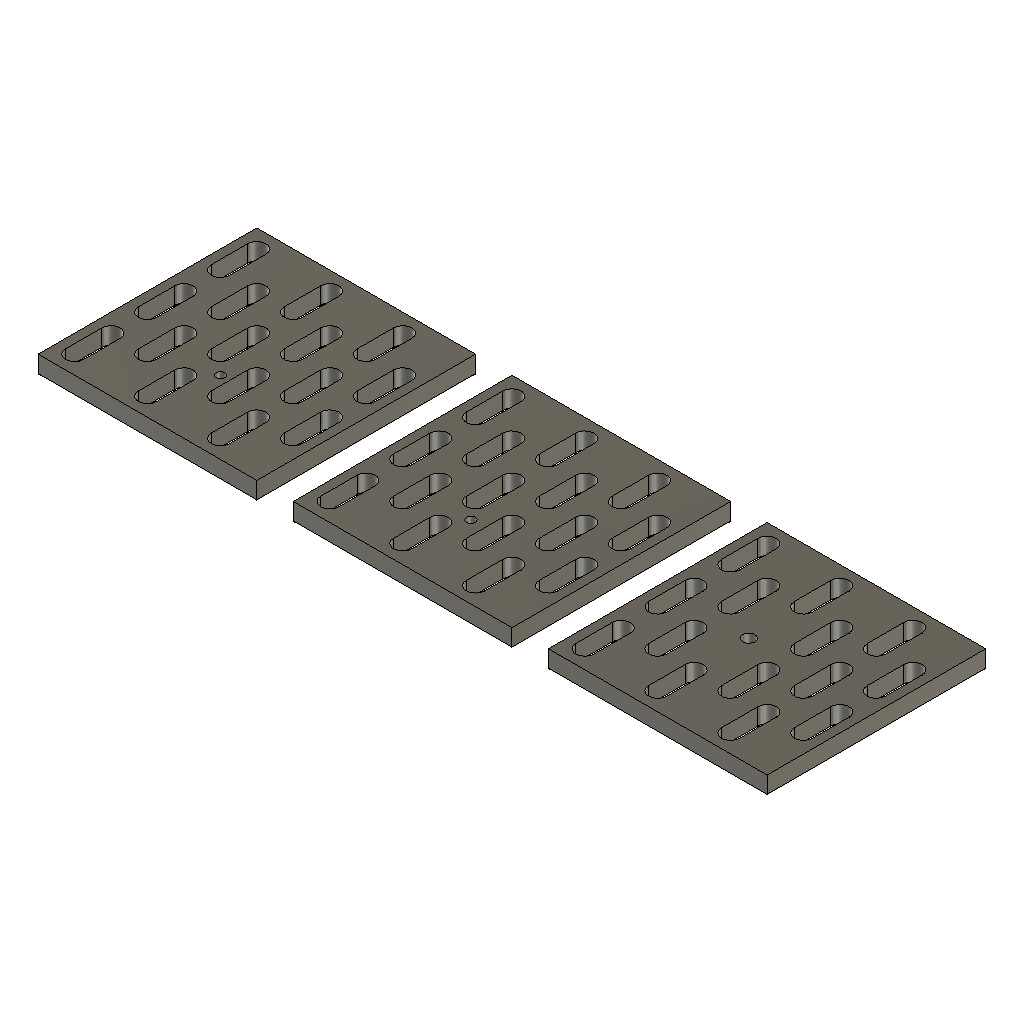
mounting-comparison (Autodesk Fusion 360 design; units mm, degrees)
part number: 2026-10-31-19-28-55-188
part number: 2026-10-31-19-28-55-479
part number: 2026-10-31-19-28-58-749
part number: 2026-10-31-19-29-04-549
Autodesk Fusion 360 part; units mm, degrees
(part 1 of 2)
sketch "Coupon blank sketch" plane through (0, 0, 0) normal (0, 0, 1) x (1, 0, 0) in component "Original M2"
  line L0 (0, 0) -> (60, 0)
  line L1 (60, 0) -> (60, 60)
  line L2 (60, 60) -> (0, 60)
  line L3 (0, 60) -> (0, 0)
  dimension "d68" = 60
  dimension "d69" = 60
  constraint horizontal L0
  constraint vertical L1
  constraint horizontal L2
  constraint vertical L3
  constraint vertical L0.start L3.end
  constraint horizontal L0.start L3.end
  measures "d68" horizontal distance of L0.start L0.end
  measures "d69" vertical distance of L0.end L1.end
extrude "Coupon blank" add sketch "Coupon blank sketch" along normal blind 5 makes body 1 in component "Original M2"
sketch "Slot 0 10 constrained seed" plane through (0, 0, 0) normal (0, 0, 1) x (1, 0, 0) in component "Original M2"
  line L0 (7.5, 5) -> (7.5, 15)
  arc A0 (7.5, 15) -> (2.5, 15) centre (5, 15) ccw
  line L1 (2.5, 15) -> (2.5, 5)
  arc A1 (2.5, 5) -> (7.5, 5) centre (5, 5) ccw
  line L2 (5, 5) -> (5, 15) construction
  line L3 (5, 5) -> (15, 5) construction
  dimension "d72" = 5
  dimension "d73" = 10
  dimension "d74" = 90
  dimension "d75" = 10
  dimension "d76" = 5
  dimension "d77" = 5
  constraint tangent L0 A0
  constraint tangent A0 L1
  constraint tangent L1 A1
  constraint tangent L0 A1
  constraint parallel L0 L1
  constraint horizontal L3
  measures "d72" diameter of A0
  measures "d73" distance of A1.centre A0.centre
  measures "d74" angle of L2 L3
  measures "d75" horizontal distance of A1.centre L3.end
  measures "d76" horizontal distance of origin A1.centre
  measures "d77" vertical distance of origin A1.centre
extrude "Slot 0 10 through cut" cut sketch "Slot 0 10 constrained seed" along normal blind 5 bodies 1 in component "Original M2"
pattern_linear "Slot 0 10 lattice" count 1 spacing 20 along (1, 0, 0) of "Slot 0 10 through cut" in component "Original M2"
sketch "Slot 0 30 constrained seed" plane through (0, 0, 0) normal (0, 0, 1) x (1, 0, 0) in component "Original M2"
  line L0 (7.5, 25) -> (7.5, 35)
  arc A0 (7.5, 35) -> (2.5, 35) centre (5, 35) ccw
  line L1 (2.5, 35) -> (2.5, 25)
  arc A1 (2.5, 25) -> (7.5, 25) centre (5, 25) ccw
  line L2 (5, 25) -> (5, 35) construction
  line L3 (5, 25) -> (15, 25) construction
  dimension "d84" = 5
  dimension "d85" = 10
  dimension "d86" = 90
  dimension "d87" = 10
  dimension "d88" = 5
  dimension "d89" = 25
  constraint tangent L0 A0
  constraint tangent A0 L1
  constraint tangent L1 A1
  constraint tangent L0 A1
  constraint parallel L0 L1
  constraint horizontal L3
  measures "d84" diameter of A0
  measures "d85" distance of A1.centre A0.centre
  measures "d86" angle of L2 L3
  measures "d87" horizontal distance of A1.centre L3.end
  measures "d88" horizontal distance of origin A1.centre
  measures "d89" vertical distance of origin A1.centre
extrude "Slot 0 30 through cut" cut sketch "Slot 0 30 constrained seed" along normal blind 5 bodies 1 in component "Original M2"
pattern_linear "Slot 0 30 lattice" count 1 spacing 20 along (1, 0, 0) of "Slot 0 30 through cut" in component "Original M2"
sketch "Slot 0 50 constrained seed" plane through (0, 0, 0) normal (0, 0, 1) x (1, 0, 0) in component "Original M2"
  line L0 (7.5, 45) -> (7.5, 55)
  arc A0 (7.5, 55) -> (2.5, 55) centre (5, 55) ccw
  line L1 (2.5, 55) -> (2.5, 45)
  arc A1 (2.5, 45) -> (7.5, 45) centre (5, 45) ccw
  line L2 (5, 45) -> (5, 55) construction
  line L3 (5, 45) -> (15, 45) construction
  dimension "d96" = 5
  dimension "d97" = 10
  dimension "d98" = 90
  dimension "d99" = 10
  dimension "d100" = 5
  dimension "d101" = 45
  constraint tangent L0 A0
  constraint tangent A0 L1
  constraint tangent L1 A1
  constraint tangent L0 A1
  constraint parallel L0 L1
  constraint horizontal L3
  measures "d96" diameter of A0
  measures "d97" distance of A1.centre A0.centre
  measures "d98" angle of L2 L3
  measures "d99" horizontal distance of A1.centre L3.end
  measures "d100" horizontal distance of origin A1.centre
  measures "d101" vertical distance of origin A1.centre
extrude "Slot 0 50 through cut" cut sketch "Slot 0 50 constrained seed" along normal blind 5 bodies 1 in component "Original M2"
pattern_linear "Slot 0 50 lattice" count 1 spacing 20 along (1, 0, 0) of "Slot 0 50 through cut" in component "Original M2"
sketch "Slot 1 20 constrained seed" plane through (0, 0, 0) normal (0, 0, 1) x (1, 0, 0) in component "Original M2"
  line L0 (17.5, 15) -> (17.5, 25)
  arc A0 (17.5, 25) -> (12.5, 25) centre (15, 25) ccw
  line L1 (12.5, 25) -> (12.5, 15)
  arc A1 (12.5, 15) -> (17.5, 15) centre (15, 15) ccw
  line L2 (15, 15) -> (15, 25) construction
  line L3 (15, 15) -> (25, 15) construction
  dimension "d108" = 5
  dimension "d109" = 10
  dimension "d110" = 90
  dimension "d111" = 10
  dimension "d112" = 15
  dimension "d113" = 15
  constraint tangent L0 A0
  constraint tangent A0 L1
  constraint tangent L1 A1
  constraint tangent L0 A1
  constraint parallel L0 L1
  constraint horizontal L3
  measures "d108" diameter of A0
  measures "d109" distance of A1.centre A0.centre
  measures "d110" angle of L2 L3
  measures "d111" horizontal distance of A1.centre L3.end
  measures "d112" horizontal distance of origin A1.centre
  measures "d113" vertical distance of origin A1.centre
extrude "Slot 1 20 through cut" cut sketch "Slot 1 20 constrained seed" along normal blind 5 bodies 1 in component "Original M2"
pattern_linear "Slot 1 20 lattice" count 1 spacing 20 along (1, 0, 0) of "Slot 1 20 through cut" in component "Original M2"
sketch "Slot 1 40 constrained seed" plane through (0, 0, 0) normal (0, 0, 1) x (1, 0, 0) in component "Original M2"
  line L0 (17.5, 35) -> (17.5, 45)
  arc A0 (17.5, 45) -> (12.5, 45) centre (15, 45) ccw
  line L1 (12.5, 45) -> (12.5, 35)
  arc A1 (12.5, 35) -> (17.5, 35) centre (15, 35) ccw
  line L2 (15, 35) -> (15, 45) construction
  line L3 (15, 35) -> (25, 35) construction
  dimension "d120" = 5
  dimension "d121" = 10
  dimension "d122" = 90
  dimension "d123" = 10
  dimension "d124" = 15
  dimension "d125" = 35
  constraint tangent L0 A0
  constraint tangent A0 L1
  constraint tangent L1 A1
  constraint tangent L0 A1
  constraint parallel L0 L1
  constraint horizontal L3
  measures "d120" diameter of A0
  measures "d121" distance of A1.centre A0.centre
  measures "d122" angle of L2 L3
  measures "d123" horizontal distance of A1.centre L3.end
  measures "d124" horizontal distance of origin A1.centre
  measures "d125" vertical distance of origin A1.centre
extrude "Slot 1 40 through cut" cut sketch "Slot 1 40 constrained seed" along normal blind 5 bodies 1 in component "Original M2"
pattern_linear "Slot 1 40 lattice" count 1 spacing 20 along (1, 0, 0) of "Slot 1 40 through cut" in component "Original M2"
sketch "Slot 2 10 constrained seed" plane through (0, 0, 0) normal (0, 0, 1) x (1, 0, 0) in component "Original M2"
  line L0 (27.5, 5) -> (27.5, 15)
  arc A0 (27.5, 15) -> (22.5, 15) centre (25, 15) ccw
  line L1 (22.5, 15) -> (22.5, 5)
  arc A1 (22.5, 5) -> (27.5, 5) centre (25, 5) ccw
  line L2 (25, 5) -> (25, 15) construction
  line L3 (25, 5) -> (35, 5) construction
  dimension "d132" = 5
  dimension "d133" = 10
  dimension "d134" = 90
  dimension "d135" = 10
  dimension "d136" = 25
  dimension "d137" = 5
  constraint tangent L0 A0
  constraint tangent A0 L1
  constraint tangent L1 A1
  constraint tangent L0 A1
  constraint parallel L0 L1
  constraint horizontal L3
  measures "d132" diameter of A0
  measures "d133" distance of A1.centre A0.centre
  measures "d134" angle of L2 L3
  measures "d135" horizontal distance of A1.centre L3.end
  measures "d136" horizontal distance of origin A1.centre
  measures "d137" vertical distance of origin A1.centre
extrude "Slot 2 10 through cut" cut sketch "Slot 2 10 constrained seed" along normal blind 5 bodies 1 in component "Original M2"
pattern_linear "Slot 2 10 lattice" count 1 spacing 20 along (1, 0, 0) of "Slot 2 10 through cut" in component "Original M2"
sketch "Slot 2 30 constrained seed" plane through (0, 0, 0) normal (0, 0, 1) x (1, 0, 0) in component "Original M2"
  line L0 (27.5, 25) -> (27.5, 35)
  arc A0 (27.5, 35) -> (22.5, 35) centre (25, 35) ccw
  line L1 (22.5, 35) -> (22.5, 25)
  arc A1 (22.5, 25) -> (27.5, 25) centre (25, 25) ccw
  line L2 (25, 25) -> (25, 35) construction
  line L3 (25, 25) -> (35, 25) construction
  dimension "d144" = 5
  dimension "d145" = 10
  dimension "d146" = 90
  dimension "d147" = 10
  dimension "d148" = 25
  dimension "d149" = 25
  constraint tangent L0 A0
  constraint tangent A0 L1
  constraint tangent L1 A1
  constraint tangent L0 A1
  constraint parallel L0 L1
  constraint horizontal L3
  measures "d144" diameter of A0
  measures "d145" distance of A1.centre A0.centre
  measures "d146" angle of L2 L3
  measures "d147" horizontal distance of A1.centre L3.end
  measures "d148" horizontal distance of origin A1.centre
  measures "d149" vertical distance of origin A1.centre
extrude "Slot 2 30 through cut" cut sketch "Slot 2 30 constrained seed" along normal blind 5 bodies 1 in component "Original M2"
pattern_linear "Slot 2 30 lattice" count 1 spacing 20 along (1, 0, 0) of "Slot 2 30 through cut" in component "Original M2"
sketch "Slot 2 50 constrained seed" plane through (0, 0, 0) normal (0, 0, 1) x (1, 0, 0) in component "Original M2"
  line L0 (27.5, 45) -> (27.5, 55)
  arc A0 (27.5, 55) -> (22.5, 55) centre (25, 55) ccw
  line L1 (22.5, 55) -> (22.5, 45)
  arc A1 (22.5, 45) -> (27.5, 45) centre (25, 45) ccw
  line L2 (25, 45) -> (25, 55) construction
  line L3 (25, 45) -> (35, 45) construction
  dimension "d156" = 5
  dimension "d157" = 10
  dimension "d158" = 90
  dimension "d159" = 10
  dimension "d160" = 25
  dimension "d161" = 45
  constraint tangent L0 A0
  constraint tangent A0 L1
  constraint tangent L1 A1
  constraint tangent L0 A1
  constraint parallel L0 L1
  constraint horizontal L3
  measures "d156" diameter of A0
  measures "d157" distance of A1.centre A0.centre
  measures "d158" angle of L2 L3
  measures "d159" horizontal distance of A1.centre L3.end
  measures "d160" horizontal distance of origin A1.centre
  measures "d161" vertical distance of origin A1.centre
extrude "Slot 2 50 through cut" cut sketch "Slot 2 50 constrained seed" along normal blind 5 bodies 1 in component "Original M2"
pattern_linear "Slot 2 50 lattice" count 1 spacing 20 along (1, 0, 0) of "Slot 2 50 through cut" in component "Original M2"
sketch "Slot 3 20 constrained seed" plane through (0, 0, 0) normal (0, 0, 1) x (1, 0, 0) in component "Original M2"
  line L0 (37.5, 15) -> (37.5, 25)
  arc A0 (37.5, 25) -> (32.5, 25) centre (35, 25) ccw
  line L1 (32.5, 25) -> (32.5, 15)
  arc A1 (32.5, 15) -> (37.5, 15) centre (35, 15) ccw
  line L2 (35, 15) -> (35, 25) construction
  line L3 (35, 15) -> (45, 15) construction
  dimension "d168" = 5
  dimension "d169" = 10
  dimension "d170" = 90
  dimension "d171" = 10
  dimension "d172" = 35
  dimension "d173" = 15
  constraint tangent L0 A0
  constraint tangent A0 L1
  constraint tangent L1 A1
  constraint tangent L0 A1
  constraint parallel L0 L1
  constraint horizontal L3
  measures "d168" diameter of A0
  measures "d169" distance of A1.centre A0.centre
  measures "d170" angle of L2 L3
  measures "d171" horizontal distance of A1.centre L3.end
  measures "d172" horizontal distance of origin A1.centre
  measures "d173" vertical distance of origin A1.centre
extrude "Slot 3 20 through cut" cut sketch "Slot 3 20 constrained seed" along normal blind 5 bodies 1 in component "Original M2"
pattern_linear "Slot 3 20 lattice" count 1 spacing 20 along (1, 0, 0) of "Slot 3 20 through cut" in component "Original M2"
sketch "Slot 3 40 constrained seed" plane through (0, 0, 0) normal (0, 0, 1) x (1, 0, 0) in component "Original M2"
  line L0 (37.5, 35) -> (37.5, 45)
  arc A0 (37.5, 45) -> (32.5, 45) centre (35, 45) ccw
  line L1 (32.5, 45) -> (32.5, 35)
  arc A1 (32.5, 35) -> (37.5, 35) centre (35, 35) ccw
  line L2 (35, 35) -> (35, 45) construction
  line L3 (35, 35) -> (45, 35) construction
  dimension "d180" = 5
  dimension "d181" = 10
  dimension "d182" = 90
  dimension "d183" = 10
  dimension "d184" = 35
  dimension "d185" = 35
  constraint tangent L0 A0
  constraint tangent A0 L1
  constraint tangent L1 A1
  constraint tangent L0 A1
  constraint parallel L0 L1
  constraint horizontal L3
  measures "d180" diameter of A0
  measures "d181" distance of A1.centre A0.centre
  measures "d182" angle of L2 L3
  measures "d183" horizontal distance of A1.centre L3.end
  measures "d184" horizontal distance of origin A1.centre
  measures "d185" vertical distance of origin A1.centre
extrude "Slot 3 40 through cut" cut sketch "Slot 3 40 constrained seed" along normal blind 5 bodies 1 in component "Original M2"
pattern_linear "Slot 3 40 lattice" count 1 spacing 20 along (1, 0, 0) of "Slot 3 40 through cut" in component "Original M2"
sketch "Slot 4 10 constrained seed" plane through (0, 0, 0) normal (0, 0, 1) x (1, 0, 0) in component "Original M2"
  line L0 (47.5, 5) -> (47.5, 15)
  arc A0 (47.5, 15) -> (42.5, 15) centre (45, 15) ccw
  line L1 (42.5, 15) -> (42.5, 5)
  arc A1 (42.5, 5) -> (47.5, 5) centre (45, 5) ccw
  line L2 (45, 5) -> (45, 15) construction
  line L3 (45, 5) -> (55, 5) construction
  dimension "d192" = 5
  dimension "d193" = 10
  dimension "d194" = 90
  dimension "d195" = 10
  dimension "d196" = 45
  dimension "d197" = 5
  constraint tangent L0 A0
  constraint tangent A0 L1
  constraint tangent L1 A1
  constraint tangent L0 A1
  constraint parallel L0 L1
  constraint horizontal L3
  measures "d192" diameter of A0
  measures "d193" distance of A1.centre A0.centre
  measures "d194" angle of L2 L3
  measures "d195" horizontal distance of A1.centre L3.end
  measures "d196" horizontal distance of origin A1.centre
  measures "d197" vertical distance of origin A1.centre
extrude "Slot 4 10 through cut" cut sketch "Slot 4 10 constrained seed" along normal blind 5 bodies 1 in component "Original M2"
pattern_linear "Slot 4 10 lattice" count 1 spacing 20 along (1, 0, 0) of "Slot 4 10 through cut" in component "Original M2"
sketch "Slot 4 30 constrained seed" plane through (0, 0, 0) normal (0, 0, 1) x (1, 0, 0) in component "Original M2"
  line L0 (47.5, 25) -> (47.5, 35)
  arc A0 (47.5, 35) -> (42.5, 35) centre (45, 35) ccw
  line L1 (42.5, 35) -> (42.5, 25)
  arc A1 (42.5, 25) -> (47.5, 25) centre (45, 25) ccw
  line L2 (45, 25) -> (45, 35) construction
  line L3 (45, 25) -> (55, 25) construction
  dimension "d204" = 5
  dimension "d205" = 10
  dimension "d206" = 90
  dimension "d207" = 10
  dimension "d208" = 45
  dimension "d209" = 25
  constraint tangent L0 A0
  constraint tangent A0 L1
  constraint tangent L1 A1
  constraint tangent L0 A1
  constraint parallel L0 L1
  constraint horizontal L3
  measures "d204" diameter of A0
  measures "d205" distance of A1.centre A0.centre
  measures "d206" angle of L2 L3
  measures "d207" horizontal distance of A1.centre L3.end
  measures "d208" horizontal distance of origin A1.centre
  measures "d209" vertical distance of origin A1.centre
extrude "Slot 4 30 through cut" cut sketch "Slot 4 30 constrained seed" along normal blind 5 bodies 1 in component "Original M2"
pattern_linear "Slot 4 30 lattice" count 1 spacing 20 along (1, 0, 0) of "Slot 4 30 through cut" in component "Original M2"
sketch "Slot 4 50 constrained seed" plane through (0, 0, 0) normal (0, 0, 1) x (1, 0, 0) in component "Original M2"
  line L0 (47.5, 45) -> (47.5, 55)
  arc A0 (47.5, 55) -> (42.5, 55) centre (45, 55) ccw
  line L1 (42.5, 55) -> (42.5, 45)
  arc A1 (42.5, 45) -> (47.5, 45) centre (45, 45) ccw
  line L2 (45, 45) -> (45, 55) construction
  line L3 (45, 45) -> (55, 45) construction
  dimension "d216" = 5
  dimension "d217" = 10
  dimension "d218" = 90
  dimension "d219" = 10
  dimension "d220" = 45
  dimension "d221" = 45
  constraint tangent L0 A0
  constraint tangent A0 L1
  constraint tangent L1 A1
  constraint tangent L0 A1
  constraint parallel L0 L1
  constraint horizontal L3
  measures "d216" diameter of A0
  measures "d217" distance of A1.centre A0.centre
  measures "d218" angle of L2 L3
  measures "d219" horizontal distance of A1.centre L3.end
  measures "d220" horizontal distance of origin A1.centre
  measures "d221" vertical distance of origin A1.centre
extrude "Slot 4 50 through cut" cut sketch "Slot 4 50 constrained seed" along normal blind 5 bodies 1 in component "Original M2"
pattern_linear "Slot 4 50 lattice" count 1 spacing 20 along (1, 0, 0) of "Slot 4 50 through cut" in component "Original M2"
sketch "Slot 5 20 constrained seed" plane through (0, 0, 0) normal (0, 0, 1) x (1, 0, 0) in component "Original M2"
  line L0 (57.5, 15) -> (57.5, 25)
  arc A0 (57.5, 25) -> (52.5, 25) centre (55, 25) ccw
  line L1 (52.5, 25) -> (52.5, 15)
  arc A1 (52.5, 15) -> (57.5, 15) centre (55, 15) ccw
  line L2 (55, 15) -> (55, 25) construction
  line L3 (55, 15) -> (65, 15) construction
  dimension "d228" = 5
  dimension "d229" = 10
  dimension "d230" = 90
  dimension "d231" = 10
  dimension "d232" = 55
  dimension "d233" = 15
  constraint tangent L0 A0
  constraint tangent A0 L1
  constraint tangent L1 A1
  constraint tangent L0 A1
  constraint parallel L0 L1
  constraint horizontal L3
  measures "d228" diameter of A0
  measures "d229" distance of A1.centre A0.centre
  measures "d230" angle of L2 L3
  measures "d231" horizontal distance of A1.centre L3.end
  measures "d232" horizontal distance of origin A1.centre
  measures "d233" vertical distance of origin A1.centre
extrude "Slot 5 20 through cut" cut sketch "Slot 5 20 constrained seed" along normal blind 5 bodies 1 in component "Original M2"
pattern_linear "Slot 5 20 lattice" count 1 spacing 20 along (1, 0, 0) of "Slot 5 20 through cut" in component "Original M2"
sketch "Slot 5 40 constrained seed" plane through (0, 0, 0) normal (0, 0, 1) x (1, 0, 0) in component "Original M2"
  line L0 (57.5, 35) -> (57.5, 45)
  arc A0 (57.5, 45) -> (52.5, 45) centre (55, 45) ccw
  line L1 (52.5, 45) -> (52.5, 35)
  arc A1 (52.5, 35) -> (57.5, 35) centre (55, 35) ccw
  line L2 (55, 35) -> (55, 45) construction
  line L3 (55, 35) -> (65, 35) construction
  dimension "d240" = 5
  dimension "d241" = 10
  dimension "d242" = 90
  dimension "d243" = 10
  dimension "d244" = 55
  dimension "d245" = 35
  constraint tangent L0 A0
  constraint tangent A0 L1
  constraint tangent L1 A1
  constraint tangent L0 A1
  constraint parallel L0 L1
  constraint horizontal L3
  measures "d240" diameter of A0
  measures "d241" distance of A1.centre A0.centre
  measures "d242" angle of L2 L3
  measures "d243" horizontal distance of A1.centre L3.end
  measures "d244" horizontal distance of origin A1.centre
  measures "d245" vertical distance of origin A1.centre
extrude "Slot 5 40 through cut" cut sketch "Slot 5 40 constrained seed" along normal blind 5 bodies 1 in component "Original M2"
pattern_linear "Slot 5 40 lattice" count 1 spacing 20 along (1, 0, 0) of "Slot 5 40 through cut" in component "Original M2"
fillet "Rounded entrances" radius 0.4 2 faces at (54.1044, 5.8357, 0) (54.1044, 5.8357, 0) on bodies 1 in component "Original M2"
sketch "Mount bore sketch" plane through (0, 0, 0) normal (0, 0, 1) x (1, 0, 0) in component "Original M2"
  circle A0 centre (30, 20) radius 1.2
  dimension "d254" = 30
  dimension "d255" = 20
  dimension "d256" = 2.4
  measures "d254" horizontal distance of origin A0.centre
  measures "d255" vertical distance of origin A0.centre
  measures "d256" diameter of A0
extrude "Mount bore" cut sketch "Mount bore sketch" along normal blind 5 bodies 1 in component "Original M2"
sketch "Flush screw seat sketch" plane through (0, 0, 0) normal (0, 0, 1) x (1, 0, 0) in component "Original M2"
  circle A0 centre (30, 20) radius 2
  dimension "d259" = 30
  dimension "d260" = 20
  dimension "d261" = 4
  measures "d259" horizontal distance of origin A0.centre
  measures "d260" vertical distance of origin A0.centre
  measures "d261" diameter of A0
extrude "Flush screw seat" cut sketch "Flush screw seat sketch" along normal blind 0.8 draft -45 bodies 1 in component "Original M2"
sketch "Coupon blank sketch (2)" plane through (0, 0, 0) normal (0, 0, 1) x (1, 0, 0) in component "Centered M2"
  line L0 (70, 0) -> (130, 0)
  line L1 (130, 0) -> (130, 60)
  line L2 (130, 60) -> (70, 60)
  line L3 (70, 60) -> (70, 0)
  dimension "d264" = 70
  dimension "d265" = 60
  dimension "d266" = 60
  constraint horizontal L0
  constraint vertical L1
  constraint horizontal L2
  constraint vertical L3
  constraint horizontal origin L0.start
  measures "d264" horizontal distance of origin L0.start
  measures "d265" horizontal distance of L0.start L0.end
  measures "d266" vertical distance of L0.end L1.end
extrude "Coupon blank'" add sketch "Coupon blank sketch (2)" along normal blind 5 separate body makes body 2 in component "Centered M2"
sketch "Slot 0 10 constrained seed (2)" plane through (0, 0, 0) normal (0, 0, 1) x (1, 0, 0) in component "Centered M2"
  line L0 (77.5, 5) -> (77.5, 15)
  arc A0 (77.5, 15) -> (72.5, 15) centre (75, 15) ccw
  line L1 (72.5, 15) -> (72.5, 5)
  arc A1 (72.5, 5) -> (77.5, 5) centre (75, 5) ccw
  line L2 (75, 5) -> (75, 15) construction
  line L3 (75, 5) -> (85, 5) construction
  dimension "d269" = 5
  dimension "d270" = 10
  dimension "d271" = 90
  dimension "d272" = 10
  dimension "d273" = 75
  dimension "d274" = 5
  constraint tangent L0 A0
  constraint tangent A0 L1
  constraint tangent L1 A1
  constraint tangent L0 A1
  constraint parallel L0 L1
  constraint horizontal L3
  measures "d269" diameter of A0
  measures "d270" distance of A1.centre A0.centre
  measures "d271" angle of L2 L3
  measures "d272" horizontal distance of A1.centre L3.end
  measures "d273" horizontal distance of origin A1.centre
  measures "d274" vertical distance of origin A1.centre
extrude "Slot 0 10 through cut'" cut sketch "Slot 0 10 constrained seed (2)" along normal blind 5 bodies 2 in component "Centered M2"
pattern_linear "Slot 0 10 lattice'" count 1 spacing 20 along (1, 0, 0) of "Slot 0 10 through cut'" in component "Centered M2"
sketch "Slot 0 30 constrained seed (2)" plane through (0, 0, 0) normal (0, 0, 1) x (1, 0, 0) in component "Centered M2"
  line L0 (77.5, 25) -> (77.5, 35)
  arc A0 (77.5, 35) -> (72.5, 35) centre (75, 35) ccw
  line L1 (72.5, 35) -> (72.5, 25)
  arc A1 (72.5, 25) -> (77.5, 25) centre (75, 25) ccw
  line L2 (75, 25) -> (75, 35) construction
  line L3 (75, 25) -> (85, 25) construction
  dimension "d281" = 5
  dimension "d282" = 10
  dimension "d283" = 90
  dimension "d284" = 10
  dimension "d285" = 75
  dimension "d286" = 25
  constraint tangent L0 A0
  constraint tangent A0 L1
  constraint tangent L1 A1
  constraint tangent L0 A1
  constraint parallel L0 L1
  constraint horizontal L3
  measures "d281" diameter of A0
  measures "d282" distance of A1.centre A0.centre
  measures "d283" angle of L2 L3
  measures "d284" horizontal distance of A1.centre L3.end
  measures "d285" horizontal distance of origin A1.centre
  measures "d286" vertical distance of origin A1.centre
extrude "Slot 0 30 through cut'" cut sketch "Slot 0 30 constrained seed (2)" along normal blind 5 bodies 2 in component "Centered M2"
pattern_linear "Slot 0 30 lattice'" count 1 spacing 20 along (1, 0, 0) of "Slot 0 30 through cut'" in component "Centered M2"
sketch "Slot 0 50 constrained seed (2)" plane through (0, 0, 0) normal (0, 0, 1) x (1, 0, 0) in component "Centered M2"
  line L0 (77.5, 45) -> (77.5, 55)
  arc A0 (77.5, 55) -> (72.5, 55) centre (75, 55) ccw
  line L1 (72.5, 55) -> (72.5, 45)
  arc A1 (72.5, 45) -> (77.5, 45) centre (75, 45) ccw
  line L2 (75, 45) -> (75, 55) construction
  line L3 (75, 45) -> (85, 45) construction
  dimension "d293" = 5
  dimension "d294" = 10
  dimension "d295" = 90
  dimension "d296" = 10
  dimension "d297" = 75
  dimension "d298" = 45
  constraint tangent L0 A0
  constraint tangent A0 L1
  constraint tangent L1 A1
  constraint tangent L0 A1
  constraint parallel L0 L1
  constraint horizontal L3
  measures "d293" diameter of A0
  measures "d294" distance of A1.centre A0.centre
  measures "d295" angle of L2 L3
  measures "d296" horizontal distance of A1.centre L3.end
  measures "d297" horizontal distance of origin A1.centre
  measures "d298" vertical distance of origin A1.centre
extrude "Slot 0 50 through cut'" cut sketch "Slot 0 50 constrained seed (2)" along normal blind 5 bodies 2 in component "Centered M2"
pattern_linear "Slot 0 50 lattice'" count 1 spacing 20 along (1, 0, 0) of "Slot 0 50 through cut'" in component "Centered M2"
sketch "Slot 1 20 constrained seed (2)" plane through (0, 0, 0) normal (0, 0, 1) x (1, 0, 0) in component "Centered M2"
  line L0 (87.5, 15) -> (87.5, 25)
  arc A0 (87.5, 25) -> (82.5, 25) centre (85, 25) ccw
  line L1 (82.5, 25) -> (82.5, 15)
  arc A1 (82.5, 15) -> (87.5, 15) centre (85, 15) ccw
  line L2 (85, 15) -> (85, 25) construction
  line L3 (85, 15) -> (95, 15) construction
  dimension "d305" = 5
  dimension "d306" = 10
  dimension "d307" = 90
  dimension "d308" = 10
  dimension "d309" = 85
  dimension "d310" = 15
  constraint tangent L0 A0
  constraint tangent A0 L1
  constraint tangent L1 A1
  constraint tangent L0 A1
  constraint parallel L0 L1
  constraint horizontal L3
  measures "d305" diameter of A0
  measures "d306" distance of A1.centre A0.centre
  measures "d307" angle of L2 L3
  measures "d308" horizontal distance of A1.centre L3.end
  measures "d309" horizontal distance of origin A1.centre
  measures "d310" vertical distance of origin A1.centre
extrude "Slot 1 20 through cut'" cut sketch "Slot 1 20 constrained seed (2)" along normal blind 5 bodies 2 in component "Centered M2"
pattern_linear "Slot 1 20 lattice'" count 1 spacing 20 along (1, 0, 0) of "Slot 1 20 through cut'" in component "Centered M2"
sketch "Slot 1 40 constrained seed (2)" plane through (0, 0, 0) normal (0, 0, 1) x (1, 0, 0) in component "Centered M2"
  line L0 (87.5, 35) -> (87.5, 45)
  arc A0 (87.5, 45) -> (82.5, 45) centre (85, 45) ccw
  line L1 (82.5, 45) -> (82.5, 35)
  arc A1 (82.5, 35) -> (87.5, 35) centre (85, 35) ccw
  line L2 (85, 35) -> (85, 45) construction
  line L3 (85, 35) -> (95, 35) construction
  dimension "d317" = 5
  dimension "d318" = 10
  dimension "d319" = 90
  dimension "d320" = 10
  dimension "d321" = 85
  dimension "d322" = 35
  constraint tangent L0 A0
  constraint tangent A0 L1
  constraint tangent L1 A1
  constraint tangent L0 A1
  constraint parallel L0 L1
  constraint horizontal L3
  measures "d317" diameter of A0
  measures "d318" distance of A1.centre A0.centre
  measures "d319" angle of L2 L3
  measures "d320" horizontal distance of A1.centre L3.end
  measures "d321" horizontal distance of origin A1.centre
  measures "d322" vertical distance of origin A1.centre
extrude "Slot 1 40 through cut'" cut sketch "Slot 1 40 constrained seed (2)" along normal blind 5 bodies 2 in component "Centered M2"
pattern_linear "Slot 1 40 lattice'" count 1 spacing 20 along (1, 0, 0) of "Slot 1 40 through cut'" in component "Centered M2"
sketch "Slot 2 10 constrained seed (2)" plane through (0, 0, 0) normal (0, 0, 1) x (1, 0, 0) in component "Centered M2"
  line L0 (97.5, 5) -> (97.5, 15)
  arc A0 (97.5, 15) -> (92.5, 15) centre (95, 15) ccw
  line L1 (92.5, 15) -> (92.5, 5)
  arc A1 (92.5, 5) -> (97.5, 5) centre (95, 5) ccw
  line L2 (95, 5) -> (95, 15) construction
  line L3 (95, 5) -> (105, 5) construction
  dimension "d329" = 5
  dimension "d330" = 10
  dimension "d331" = 90
  dimension "d332" = 10
  dimension "d333" = 95
  dimension "d334" = 5
  constraint tangent L0 A0
  constraint tangent A0 L1
  constraint tangent L1 A1
  constraint tangent L0 A1
  constraint parallel L0 L1
  constraint horizontal L3
  measures "d329" diameter of A0
  measures "d330" distance of A1.centre A0.centre
  measures "d331" angle of L2 L3
  measures "d332" horizontal distance of A1.centre L3.end
  measures "d333" horizontal distance of origin A1.centre
  measures "d334" vertical distance of origin A1.centre
extrude "Slot 2 10 through cut'" cut sketch "Slot 2 10 constrained seed (2)" along normal blind 5 bodies 2 in component "Centered M2"
pattern_linear "Slot 2 10 lattice'" count 1 spacing 20 along (1, 0, 0) of "Slot 2 10 through cut'" in component "Centered M2"
sketch "Slot 2 30 constrained seed (2)" plane through (0, 0, 0) normal (0, 0, 1) x (1, 0, 0) in component "Centered M2"
  line L0 (97.5, 25) -> (97.5, 35)
  arc A0 (97.5, 35) -> (92.5, 35) centre (95, 35) ccw
  line L1 (92.5, 35) -> (92.5, 25)
  arc A1 (92.5, 25) -> (97.5, 25) centre (95, 25) ccw
  line L2 (95, 25) -> (95, 35) construction
  line L3 (95, 25) -> (105, 25) construction
  dimension "d341" = 5
  dimension "d342" = 10
  dimension "d343" = 90
  dimension "d344" = 10
  dimension "d345" = 95
  dimension "d346" = 25
  constraint tangent L0 A0
  constraint tangent A0 L1
  constraint tangent L1 A1
  constraint tangent L0 A1
  constraint parallel L0 L1
  constraint horizontal L3
  measures "d341" diameter of A0
  measures "d342" distance of A1.centre A0.centre
  measures "d343" angle of L2 L3
  measures "d344" horizontal distance of A1.centre L3.end
  measures "d345" horizontal distance of origin A1.centre
  measures "d346" vertical distance of origin A1.centre
extrude "Slot 2 30 through cut'" cut sketch "Slot 2 30 constrained seed (2)" along normal blind 5 bodies 2 in component "Centered M2"
pattern_linear "Slot 2 30 lattice'" count 1 spacing 20 along (1, 0, 0) of "Slot 2 30 through cut'" in component "Centered M2"
sketch "Slot 2 50 constrained seed (2)" plane through (0, 0, 0) normal (0, 0, 1) x (1, 0, 0) in component "Centered M2"
  line L0 (97.5, 45) -> (97.5, 55)
  arc A0 (97.5, 55) -> (92.5, 55) centre (95, 55) ccw
  line L1 (92.5, 55) -> (92.5, 45)
  arc A1 (92.5, 45) -> (97.5, 45) centre (95, 45) ccw
  line L2 (95, 45) -> (95, 55) construction
  line L3 (95, 45) -> (105, 45) construction
  dimension "d353" = 5
  dimension "d354" = 10
  dimension "d355" = 90
  dimension "d356" = 10
  dimension "d357" = 95
  dimension "d358" = 45
  constraint tangent L0 A0
  constraint tangent A0 L1
  constraint tangent L1 A1
  constraint tangent L0 A1
  constraint parallel L0 L1
  constraint horizontal L3
  measures "d353" diameter of A0
  measures "d354" distance of A1.centre A0.centre
  measures "d355" angle of L2 L3
  measures "d356" horizontal distance of A1.centre L3.end
  measures "d357" horizontal distance of origin A1.centre
  measures "d358" vertical distance of origin A1.centre
extrude "Slot 2 50 through cut'" cut sketch "Slot 2 50 constrained seed (2)" along normal blind 5 bodies 2 in component "Centered M2"
pattern_linear "Slot 2 50 lattice'" count 1 spacing 20 along (1, 0, 0) of "Slot 2 50 through cut'" in component "Centered M2"
sketch "Slot 3 20 constrained seed (2)" plane through (0, 0, 0) normal (0, 0, 1) x (1, 0, 0) in component "Centered M2"
  line L0 (107.5, 15) -> (107.5, 25)
  arc A0 (107.5, 25) -> (102.5, 25) centre (105, 25) ccw
  line L1 (102.5, 25) -> (102.5, 15)
  arc A1 (102.5, 15) -> (107.5, 15) centre (105, 15) ccw
  line L2 (105, 15) -> (105, 25) construction
  line L3 (105, 15) -> (115, 15) construction
  dimension "d365" = 5
  dimension "d366" = 10
  dimension "d367" = 90
  dimension "d368" = 10
  dimension "d369" = 105
  dimension "d370" = 15
  constraint tangent L0 A0
  constraint tangent A0 L1
  constraint tangent L1 A1
  constraint tangent L0 A1
  constraint parallel L0 L1
  constraint horizontal L3
  measures "d365" diameter of A0
  measures "d366" distance of A1.centre A0.centre
  measures "d367" angle of L2 L3
  measures "d368" horizontal distance of A1.centre L3.end
  measures "d369" horizontal distance of origin A1.centre
  measures "d370" vertical distance of origin A1.centre
extrude "Slot 3 20 through cut'" cut sketch "Slot 3 20 constrained seed (2)" along normal blind 5 bodies 2 in component "Centered M2"
pattern_linear "Slot 3 20 lattice'" count 1 spacing 20 along (1, 0, 0) of "Slot 3 20 through cut'" in component "Centered M2"
sketch "Slot 3 40 constrained seed (2)" plane through (0, 0, 0) normal (0, 0, 1) x (1, 0, 0) in component "Centered M2"
  line L0 (107.5, 35) -> (107.5, 45)
  arc A0 (107.5, 45) -> (102.5, 45) centre (105, 45) ccw
  line L1 (102.5, 45) -> (102.5, 35)
  arc A1 (102.5, 35) -> (107.5, 35) centre (105, 35) ccw
  line L2 (105, 35) -> (105, 45) construction
  line L3 (105, 35) -> (115, 35) construction
  dimension "d377" = 5
  dimension "d378" = 10
  dimension "d379" = 90
  dimension "d380" = 10
  dimension "d381" = 105
  dimension "d382" = 35
  constraint tangent L0 A0
  constraint tangent A0 L1
  constraint tangent L1 A1
  constraint tangent L0 A1
  constraint parallel L0 L1
  constraint horizontal L3
  measures "d377" diameter of A0
  measures "d378" distance of A1.centre A0.centre
  measures "d379" angle of L2 L3
  measures "d380" horizontal distance of A1.centre L3.end
  measures "d381" horizontal distance of origin A1.centre
  measures "d382" vertical distance of origin A1.centre
extrude "Slot 3 40 through cut'" cut sketch "Slot 3 40 constrained seed (2)" along normal blind 5 bodies 2 in component "Centered M2"
pattern_linear "Slot 3 40 lattice'" count 1 spacing 20 along (1, 0, 0) of "Slot 3 40 through cut'" in component "Centered M2"
sketch "Slot 4 10 constrained seed (2)" plane through (0, 0, 0) normal (0, 0, 1) x (1, 0, 0) in component "Centered M2"
  line L0 (117.5, 5) -> (117.5, 15)
  arc A0 (117.5, 15) -> (112.5, 15) centre (115, 15) ccw
  line L1 (112.5, 15) -> (112.5, 5)
  arc A1 (112.5, 5) -> (117.5, 5) centre (115, 5) ccw
  line L2 (115, 5) -> (115, 15) construction
  line L3 (115, 5) -> (125, 5) construction
  dimension "d389" = 5
  dimension "d390" = 10
  dimension "d391" = 90
  dimension "d392" = 10
  dimension "d393" = 115
  dimension "d394" = 5
  constraint tangent L0 A0
  constraint tangent A0 L1
  constraint tangent L1 A1
  constraint tangent L0 A1
  constraint parallel L0 L1
  constraint horizontal L3
  measures "d389" diameter of A0
  measures "d390" distance of A1.centre A0.centre
  measures "d391" angle of L2 L3
  measures "d392" horizontal distance of A1.centre L3.end
  measures "d393" horizontal distance of origin A1.centre
  measures "d394" vertical distance of origin A1.centre
extrude "Slot 4 10 through cut'" cut sketch "Slot 4 10 constrained seed (2)" along normal blind 5 bodies 2 in component "Centered M2"
pattern_linear "Slot 4 10 lattice'" count 1 spacing 20 along (1, 0, 0) of "Slot 4 10 through cut'" in component "Centered M2"
sketch "Slot 4 30 constrained seed (2)" plane through (0, 0, 0) normal (0, 0, 1) x (1, 0, 0) in component "Centered M2"
  line L0 (117.5, 25) -> (117.5, 35)
  arc A0 (117.5, 35) -> (112.5, 35) centre (115, 35) ccw
  line L1 (112.5, 35) -> (112.5, 25)
  arc A1 (112.5, 25) -> (117.5, 25) centre (115, 25) ccw
  line L2 (115, 25) -> (115, 35) construction
  line L3 (115, 25) -> (125, 25) construction
  dimension "d401" = 5
  dimension "d402" = 10
  dimension "d403" = 90
  dimension "d404" = 10
  dimension "d405" = 115
  dimension "d406" = 25
  constraint tangent L0 A0
  constraint tangent A0 L1
  constraint tangent L1 A1
  constraint tangent L0 A1
  constraint parallel L0 L1
  constraint horizontal L3
  measures "d401" diameter of A0
  measures "d402" distance of A1.centre A0.centre
  measures "d403" angle of L2 L3
  measures "d404" horizontal distance of A1.centre L3.end
  measures "d405" horizontal distance of origin A1.centre
  measures "d406" vertical distance of origin A1.centre
extrude "Slot 4 30 through cut'" cut sketch "Slot 4 30 constrained seed (2)" along normal blind 5 bodies 2 in component "Centered M2"
pattern_linear "Slot 4 30 lattice'" count 1 spacing 20 along (1, 0, 0) of "Slot 4 30 through cut'" in component "Centered M2"
sketch "Slot 4 50 constrained seed (2)" plane through (0, 0, 0) normal (0, 0, 1) x (1, 0, 0) in component "Centered M2"
  line L0 (117.5, 45) -> (117.5, 55)
  arc A0 (117.5, 55) -> (112.5, 55) centre (115, 55) ccw
  line L1 (112.5, 55) -> (112.5, 45)
  arc A1 (112.5, 45) -> (117.5, 45) centre (115, 45) ccw
  line L2 (115, 45) -> (115, 55) construction
  line L3 (115, 45) -> (125, 45) construction
  dimension "d413" = 5
  dimension "d414" = 10
  dimension "d415" = 90
  dimension "d416" = 10
  dimension "d417" = 115
  dimension "d418" = 45
  constraint tangent L0 A0
  constraint tangent A0 L1
  constraint tangent L1 A1
  constraint tangent L0 A1
  constraint parallel L0 L1
  constraint horizontal L3
  measures "d413" diameter of A0
  measures "d414" distance of A1.centre A0.centre
  measures "d415" angle of L2 L3
  measures "d416" horizontal distance of A1.centre L3.end
  measures "d417" horizontal distance of origin A1.centre
  measures "d418" vertical distance of origin A1.centre
extrude "Slot 4 50 through cut'" cut sketch "Slot 4 50 constrained seed (2)" along normal blind 5 bodies 2 in component "Centered M2"
pattern_linear "Slot 4 50 lattice'" count 1 spacing 20 along (1, 0, 0) of "Slot 4 50 through cut'" in component "Centered M2"
sketch "Slot 5 20 constrained seed (2)" plane through (0, 0, 0) normal (0, 0, 1) x (1, 0, 0) in component "Centered M2"
  line L0 (127.5, 15) -> (127.5, 25)
  arc A0 (127.5, 25) -> (122.5, 25) centre (125, 25) ccw
  line L1 (122.5, 25) -> (122.5, 15)
  arc A1 (122.5, 15) -> (127.5, 15) centre (125, 15) ccw
  line L2 (125, 15) -> (125, 25) construction
  line L3 (125, 15) -> (135, 15) construction
  dimension "d425" = 5
  dimension "d426" = 10
  dimension "d427" = 90
  dimension "d428" = 10
  dimension "d429" = 125
  dimension "d430" = 15
  constraint tangent L0 A0
  constraint tangent A0 L1
  constraint tangent L1 A1
  constraint tangent L0 A1
  constraint parallel L0 L1
  constraint horizontal L3
  measures "d425" diameter of A0
  measures "d426" distance of A1.centre A0.centre
  measures "d427" angle of L2 L3
  measures "d428" horizontal distance of A1.centre L3.end
  measures "d429" horizontal distance of origin A1.centre
  measures "d430" vertical distance of origin A1.centre
extrude "Slot 5 20 through cut'" cut sketch "Slot 5 20 constrained seed (2)" along normal blind 5 bodies 2 in component "Centered M2"
pattern_linear "Slot 5 20 lattice'" count 1 spacing 20 along (1, 0, 0) of "Slot 5 20 through cut'" in component "Centered M2"
sketch "Slot 5 40 constrained seed (2)" plane through (0, 0, 0) normal (0, 0, 1) x (1, 0, 0) in component "Centered M2"
  line L0 (127.5, 35) -> (127.5, 45)
  arc A0 (127.5, 45) -> (122.5, 45) centre (125, 45) ccw
  line L1 (122.5, 45) -> (122.5, 35)
  arc A1 (122.5, 35) -> (127.5, 35) centre (125, 35) ccw
  line L2 (125, 35) -> (125, 45) construction
  line L3 (125, 35) -> (135, 35) construction
  dimension "d437" = 5
  dimension "d438" = 10
  dimension "d439" = 90
  dimension "d440" = 10
  dimension "d441" = 125
  dimension "d442" = 35
  constraint tangent L0 A0
  constraint tangent A0 L1
  constraint tangent L1 A1
  constraint tangent L0 A1
  constraint parallel L0 L1
  constraint horizontal L3
  measures "d437" diameter of A0
  measures "d438" distance of A1.centre A0.centre
  measures "d439" angle of L2 L3
  measures "d440" horizontal distance of A1.centre L3.end
  measures "d441" horizontal distance of origin A1.centre
  measures "d442" vertical distance of origin A1.centre
extrude "Slot 5 40 through cut'" cut sketch "Slot 5 40 constrained seed (2)" along normal blind 5 bodies 2 in component "Centered M2"
pattern_linear "Slot 5 40 lattice'" count 1 spacing 20 along (1, 0, 0) of "Slot 5 40 through cut'" in component "Centered M2"
fillet "Rounded entrances'" radius 0.4 2 faces at (124.1044, 5.8357, 0) (124.1044, 5.8357, 0) on bodies 2 in component "Centered M2"
sketch "Mount bore sketch (2)" plane through (0, 0, 0) normal (0, 0, 1) x (1, 0, 0) in component "Centered M2"
  circle A0 centre (98.75, 20) radius 1.2
  dimension "d451" = 98.75
  dimension "d452" = 20
  dimension "d453" = 2.4
  measures "d451" horizontal distance of origin A0.centre
  measures "d452" vertical distance of origin A0.centre
  measures "d453" diameter of A0
extrude "Mount bore'" cut sketch "Mount bore sketch (2)" along normal blind 5 bodies 2 in component "Centered M2"
sketch "Flush screw seat sketch (2)" plane through (0, 0, 0) normal (0, 0, 1) x (1, 0, 0) in component "Centered M2"
  circle A0 centre (98.75, 20) radius 2
  dimension "d456" = 98.75
  dimension "d457" = 20
  dimension "d458" = 4
  measures "d456" horizontal distance of origin A0.centre
  measures "d457" vertical distance of origin A0.centre
  measures "d458" diameter of A0
extrude "Flush screw seat'" cut sketch "Flush screw seat sketch (2)" along normal blind 0.8 draft -45 bodies 2 in component "Centered M2"
sketch "Coupon blank sketch (3)" plane through (0, 0, 0) normal (0, 0, 1) x (1, 0, 0) in component "Solid-land M3"
  line L0 (140, 0) -> (200, 0)
  line L1 (200, 0) -> (200, 60)
  line L2 (200, 60) -> (140, 60)
  line L3 (140, 60) -> (140, 0)
  dimension "d461" = 140
  dimension "d462" = 60
  dimension "d463" = 60
  constraint horizontal L0
  constraint vertical L1
  constraint horizontal L2
  constraint vertical L3
  constraint horizontal origin L0.start
  measures "d461" horizontal distance of origin L0.start
  measures "d462" horizontal distance of L0.start L0.end
  measures "d463" vertical distance of L0.end L1.end
extrude "Coupon blank''" add sketch "Coupon blank sketch (3)" along normal blind 5 separate body makes body 3 in component "Solid-land M3"
sketch "Slot 0 10 constrained seed (3)" plane through (0, 0, 0) normal (0, 0, 1) x (1, 0, 0) in component "Solid-land M3"
  line L0 (147.5, 5) -> (147.5, 15)
  arc A0 (147.5, 15) -> (142.5, 15) centre (145, 15) ccw
  line L1 (142.5, 15) -> (142.5, 5)
  arc A1 (142.5, 5) -> (147.5, 5) centre (145, 5) ccw
  line L2 (145, 5) -> (145, 15) construction
  line L3 (145, 5) -> (155, 5) construction
  dimension "d466" = 5
  dimension "d467" = 10
  dimension "d468" = 90
  dimension "d469" = 10
  dimension "d470" = 145
  dimension "d471" = 5
  constraint tangent L0 A0
  constraint tangent A0 L1
  constraint tangent L1 A1
  constraint tangent L0 A1
  constraint parallel L0 L1
  constraint horizontal L3
  measures "d466" diameter of A0
  measures "d467" distance of A1.centre A0.centre
  measures "d468" angle of L2 L3
  measures "d469" horizontal distance of A1.centre L3.end
  measures "d470" horizontal distance of origin A1.centre
  measures "d471" vertical distance of origin A1.centre
extrude "Slot 0 10 through cut''" cut sketch "Slot 0 10 constrained seed (3)" along normal blind 5 bodies 3 in component "Solid-land M3"
pattern_linear "Slot 0 10 lattice''" count 1 spacing 20 along (1, 0, 0) of "Slot 0 10 through cut''" in component "Solid-land M3"
sketch "Slot 0 30 constrained seed (3)" plane through (0, 0, 0) normal (0, 0, 1) x (1, 0, 0) in component "Solid-land M3"
  line L0 (147.5, 25) -> (147.5, 35)
  arc A0 (147.5, 35) -> (142.5, 35) centre (145, 35) ccw
  line L1 (142.5, 35) -> (142.5, 25)
  arc A1 (142.5, 25) -> (147.5, 25) centre (145, 25) ccw
  line L2 (145, 25) -> (145, 35) construction
  line L3 (145, 25) -> (155, 25) construction
  dimension "d478" = 5
  dimension "d479" = 10
  dimension "d480" = 90
  dimension "d481" = 10
  dimension "d482" = 145
  dimension "d483" = 25
  constraint tangent L0 A0
  constraint tangent A0 L1
  constraint tangent L1 A1
  constraint tangent L0 A1
  constraint parallel L0 L1
  constraint horizontal L3
  measures "d478" diameter of A0
  measures "d479" distance of A1.centre A0.centre
  measures "d480" angle of L2 L3
  measures "d481" horizontal distance of A1.centre L3.end
  measures "d482" horizontal distance of origin A1.centre
  measures "d483" vertical distance of origin A1.centre
extrude "Slot 0 30 through cut''" cut sketch "Slot 0 30 constrained seed (3)" along normal blind 5 bodies 3 in component "Solid-land M3"
pattern_linear "Slot 0 30 lattice''" count 1 spacing 20 along (1, 0, 0) of "Slot 0 30 through cut''" in component "Solid-land M3"
sketch "Slot 0 50 constrained seed (3)" plane through (0, 0, 0) normal (0, 0, 1) x (1, 0, 0) in component "Solid-land M3"
  line L0 (147.5, 45) -> (147.5, 55)
  arc A0 (147.5, 55) -> (142.5, 55) centre (145, 55) ccw
  line L1 (142.5, 55) -> (142.5, 45)
  arc A1 (142.5, 45) -> (147.5, 45) centre (145, 45) ccw
  line L2 (145, 45) -> (145, 55) construction
  line L3 (145, 45) -> (155, 45) construction
  dimension "d490" = 5
  dimension "d491" = 10
  dimension "d492" = 90
  dimension "d493" = 10
  dimension "d494" = 145
  dimension "d495" = 45
  constraint tangent L0 A0
  constraint tangent A0 L1
  constraint tangent L1 A1
  constraint tangent L0 A1
  constraint parallel L0 L1
  constraint horizontal L3
  measures "d490" diameter of A0
  measures "d491" distance of A1.centre A0.centre
  measures "d492" angle of L2 L3
  measures "d493" horizontal distance of A1.centre L3.end
  measures "d494" horizontal distance of origin A1.centre
  measures "d495" vertical distance of origin A1.centre
extrude "Slot 0 50 through cut''" cut sketch "Slot 0 50 constrained seed (3)" along normal blind 5 bodies 3 in component "Solid-land M3"
pattern_linear "Slot 0 50 lattice''" count 1 spacing 20 along (1, 0, 0) of "Slot 0 50 through cut''" in component "Solid-land M3"
sketch "Slot 1 20 constrained seed (3)" plane through (0, 0, 0) normal (0, 0, 1) x (1, 0, 0) in component "Solid-land M3"
  line L0 (157.5, 15) -> (157.5, 25)
  arc A0 (157.5, 25) -> (152.5, 25) centre (155, 25) ccw
  line L1 (152.5, 25) -> (152.5, 15)
  arc A1 (152.5, 15) -> (157.5, 15) centre (155, 15) ccw
  line L2 (155, 15) -> (155, 25) construction
  line L3 (155, 15) -> (165, 15) construction
  dimension "d502" = 5
  dimension "d503" = 10
  dimension "d504" = 90
  dimension "d505" = 10
  dimension "d506" = 155
  dimension "d507" = 15
  constraint tangent L0 A0
  constraint tangent A0 L1
  constraint tangent L1 A1
  constraint tangent L0 A1
  constraint parallel L0 L1
  constraint horizontal L3
  measures "d502" diameter of A0
  measures "d503" distance of A1.centre A0.centre
  measures "d504" angle of L2 L3
  measures "d505" horizontal distance of A1.centre L3.end
  measures "d506" horizontal distance of origin A1.centre
  measures "d507" vertical distance of origin A1.centre
extrude "Slot 1 20 through cut''" cut sketch "Slot 1 20 constrained seed (3)" along normal blind 5 bodies 3 in component "Solid-land M3"
pattern_linear "Slot 1 20 lattice''" count 1 spacing 20 along (1, 0, 0) of "Slot 1 20 through cut''" in component "Solid-land M3"
sketch "Slot 1 40 constrained seed (3)" plane through (0, 0, 0) normal (0, 0, 1) x (1, 0, 0) in component "Solid-land M3"
  line L0 (157.5, 35) -> (157.5, 45)
  arc A0 (157.5, 45) -> (152.5, 45) centre (155, 45) ccw
  line L1 (152.5, 45) -> (152.5, 35)
  arc A1 (152.5, 35) -> (157.5, 35) centre (155, 35) ccw
  line L2 (155, 35) -> (155, 45) construction
  line L3 (155, 35) -> (165, 35) construction
  dimension "d514" = 5
  dimension "d515" = 10
  dimension "d516" = 90
  dimension "d517" = 10
  dimension "d518" = 155
  dimension "d519" = 35
  constraint tangent L0 A0
  constraint tangent A0 L1
  constraint tangent L1 A1
  constraint tangent L0 A1
  constraint parallel L0 L1
  constraint horizontal L3
  measures "d514" diameter of A0
  measures "d515" distance of A1.centre A0.centre
  measures "d516" angle of L2 L3
  measures "d517" horizontal distance of A1.centre L3.end
  measures "d518" horizontal distance of origin A1.centre
  measures "d519" vertical distance of origin A1.centre
extrude "Slot 1 40 through cut''" cut sketch "Slot 1 40 constrained seed (3)" along normal blind 5 bodies 3 in component "Solid-land M3"
pattern_linear "Slot 1 40 lattice''" count 1 spacing 20 along (1, 0, 0) of "Slot 1 40 through cut''" in component "Solid-land M3"
sketch "Slot 2 10 constrained seed (3)" plane through (0, 0, 0) normal (0, 0, 1) x (1, 0, 0) in component "Solid-land M3"
  line L0 (167.5, 5) -> (167.5, 15)
  arc A0 (167.5, 15) -> (162.5, 15) centre (165, 15) ccw
  line L1 (162.5, 15) -> (162.5, 5)
  arc A1 (162.5, 5) -> (167.5, 5) centre (165, 5) ccw
  line L2 (165, 5) -> (165, 15) construction
  line L3 (165, 5) -> (175, 5) construction
  dimension "d526" = 5
  dimension "d527" = 10
  dimension "d528" = 90
  dimension "d529" = 10
  dimension "d530" = 165
  dimension "d531" = 5
  constraint tangent L0 A0
  constraint tangent A0 L1
  constraint tangent L1 A1
  constraint tangent L0 A1
  constraint parallel L0 L1
  constraint horizontal L3
  measures "d526" diameter of A0
  measures "d527" distance of A1.centre A0.centre
  measures "d528" angle of L2 L3
  measures "d529" horizontal distance of A1.centre L3.end
  measures "d530" horizontal distance of origin A1.centre
  measures "d531" vertical distance of origin A1.centre
extrude "Slot 2 10 through cut''" cut sketch "Slot 2 10 constrained seed (3)" along normal blind 5 bodies 3 in component "Solid-land M3"
pattern_linear "Slot 2 10 lattice''" count 1 spacing 20 along (1, 0, 0) of "Slot 2 10 through cut''" in component "Solid-land M3"